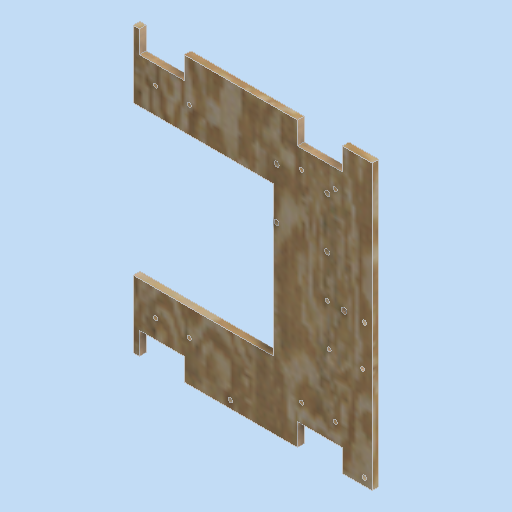
# Autodesk Inventor part: plateau_grand_robot
Saved by Autodesk Inventor 2026 (Build 300175050, 175E)
## iProperties
Created: 2025-05-01
Part Number: plateau_grand_robot
Material: Holz (Ahorn)
Document SubType Name: Modeling
Designer: karle
Density: 0.67 g/cm^3
Appearance: Ahorn - natur - glänzend - dunkel getönt
Author: karle
Autodesk Inventor part; units mm, degrees
ref_plane "YZ Plane" through (0, 0, 0) normal (1, 0, 0) x (0, 1, 0)
ref_plane "XZ Plane" through (0, 0, 0) normal (0, 1, 0) x (-1, 0, 0)
ref_plane "XY Plane" through (0, 0, 0) normal (0, 0, 1) x (1, 0, 0)
sketch "Skizze1" plane through (0, 0, 0) normal (0, 1, 0) x (-1, 0, 0)
  line L0 (175, 190) -> (-175, 190)
  line L1 (-175, 190) -> (-175, -190)
  line L2 (-175, -190) -> (175, -190)
  line L3 (175, -190) -> (175, 190)
  point P0 (0, 0)
  dimension "d0" = 380
  dimension "d1" = 350
  dimension "d2" = 175
  dimension "d3" = 190
  constraints: 8 end point, 2 parallel, 1 horizontal, 1 perpendicular
  measures "d0" distance between parallel lines of L2 L0
  measures "d1" distance of L1.end L2.end
  measures "d2" distance from line of point (0, 0) L3
  measures "d3" distance from line of L0 point (0, 0)
extrude "Extrusion1" add sketch "Skizze1" against normal blind 9
sketch "Skizze3" plane through (0, 0, 0) normal (0, 1, 0) x (1, 0, 0)
  line L0 (-175, 190) -> (-175, -190) projected
  line L1 (-175, -190) -> (175, -190) projected
  line L2 (175, 190) -> (175, -190) projected
  line L3 (175, -190) -> (-175, -190) projected
  line L4 (-175, -190) -> (-175, 190) projected
  line L5 (-175, 190) -> (175, 190) projected
  point P0 (0, 0)
  point P1 (165, 0)
  point P2 (115, 0)
  point P3 (-15, 180)
  point P4 (165, 180)
  point P5 (175, 0)
  dimension "d29" = 10
  dimension "d96" = 10
  dimension "d97" = 180
  dimension "d99" = 60
  dimension "d100" = 10
  dimension "d101" = 190
  constraints: 1 horizontal alignment, 1 midpoint, 1 vertical alignment
  measures "d29" distance from line of L5 point (165, 180)
  measures "d96" distance from line of point (-15, 180) L5
  measures "d97" distance of point (165, 180) point (-15, 180)
  measures "d99" distance of point (175, 0) point (115, 0)
  measures "d100" distance from line of L2 point (165, 0)
  measures "d101" distance from line of L5 point (115, 0)
hole "Bohrung2" at (165, 0, 0) at (115, 0, 0) at (-15, 0, -180) at (165, 0, -180) direction (0, -1, 0) diameter 6 end through all
sketch "Skizze4" plane through (0, -9, 0) normal (0, -1, 0) x (1, 0, 0)
  line L0 (-175, -190) -> (175, -190) projected
  line L1 (-175, 190) -> (-175, -190) projected
  line L2 (175, 190) -> (-175, 190) projected
  line L3 (175, -190) -> (175, 190) projected
  point P0 (0, 0)
  point P1 (115, 125)
  point P2 (115, 57)
  point P3 (47, 57)
  point P4 (47, 125)
  dimension "d30" = 68
  dimension "d31" = 68
  dimension "d41" = 65
  dimension "d42" = 60
  constraints: 2 horizontal alignment, 2 vertical alignment
  measures "d30" distance of point (115, 57) point (115, 125)
  measures "d31" distance of point (115, 57) point (47, 57)
  measures "d41" distance from line of L2 point (115, 125)
  measures "d42" distance from line of L3 point (115, 57)
hole "Bohrung3" at (115, -9, 125) at (115, -9, 57) at (47, -9, 57) at (47, -9, 125) direction (0, 1, 0) diameter 7 end through all
sketch "Skizze6" plane through (0, 0, 0) normal (0, 1, 0) x (1, 0, 0)
  line L0 (-175, 190) -> (-175, -190) projected
  line L1 (-175, -100) -> (42.5, -100)
  line L2 (42.5, -100) -> (42.5, 100)
  line L3 (42.5, 100) -> (-175, 100)
  line L4 (-175, 100) -> (-175, -100)
  line L5 (-175, -190) -> (-145, -190)
  line L6 (-145, -190) -> (-145, -100)
  line L7 (-145, -100) -> (-175, -100)
  line L8 (-175, -100) -> (-175, -190)
  line L9 (-175, 190) -> (-145, 190)
  line L10 (-145, 190) -> (-145, 100)
  line L11 (-145, 100) -> (-175, 100)
  line L12 (-175, 100) -> (-175, 190)
  point P0 (0, 0)
  dimension "d48" = 100
  dimension "d49" = 200
  dimension "d50" = 217.5
  dimension "d112" = 30
  dimension "d113" = 30
  constraints: 24 end point, 6 parallel, 3 horizontal, 3 perpendicular, 3 point on line
  measures "d48" distance from line of point (0, 0) L1
  measures "d49" distance between parallel lines of L1 L3
  measures "d50" distance between parallel lines of L0 L2
  measures "d112" distance between parallel lines of L0 L6
  measures "d113" distance between parallel lines of L0 L10
extrude "Extrusion3" cut sketch "Skizze6" against normal blind 88
sketch "Sketch11" plane through (0, 0, 0) normal (0, 1, 0) x (1, 0, 0)
  line L0 (79.1821, 0) -> (171.9168, 0) construction
  line L1 (175, -190) -> (175, 190) construction
  point P0 (0, 0)
  point P1 (137.5, 0)
  dimension "d117" = 37.5
  constraints: 2 end point, 1 horizontal, 1 point on line
  measures "d117" distance from line of L1 point (137.5, 0)
hole "Hole8" at (137.5, 0, 0) direction (0, -1, 0) diameter 8 end through all
sketch "Sketch10" plane through (0, 0, 0) normal (0, 1, 0) x (1, 0, 0)
  line L0 (-115, -135) -> (-70, -135) construction
  line L1 (5.2625, -294.5203) -> (5.2625, 225.0772) construction
  line L2 (-230.0493, 0) -> (259.3232, 0) construction
  line L3 (-175, -190) -> (175, -190) construction
  line L4 (-175, -100) -> (-175, -190) construction
  line L5 (125.525, -135) -> (80.525, -135) construction
  line L6 (-115, 135) -> (-70, 135) construction
  line L7 (125.525, 135) -> (80.525, 135) construction
  line L8 (117.5, 55) -> (162.5, 55) construction
  line L9 (175, 190) -> (-145, 190) construction
  line L10 (175, -190) -> (175, 190) construction
  line L11 (-145, -190) -> (-145, -100) projected
  point P0 (0, 0)
  dimension "d102" = 55
  dimension "d103" = 45
  dimension "d114" = 135
  dimension "d115" = 45
  dimension "d116" = 12.5
  dimension "d143" = 30
  dimension "d144" = 49.475
  constraints: 14 end point, 12 symmetric about line, 10 coincident, 3 horizontal, 1 vertical
  measures "d102" distance between parallel lines of L3 L0
  measures "d103" distance of point (-70, -135) point (-115, -135)
  measures "d114" distance between parallel lines of L9 L8
  measures "d115" distance of L8.start L8.end
  measures "d116" distance from line of L10 point (162.5, 55)
  measures "d143" distance from line of point (-115, -135) L11
  measures "d144" distance from line of L10 point (125.525, 135)
hole "Hole7" at (-115, 0, 135) at (-70, 0, 135) at (80.525, 0, 135) at (125.525, 0, 135) at (-70, 0, -135) at (-115, 0, -135) at (125.525, 0, -135) at (80.525, 0, -135) at (162.5, 0, -55) at (117.5, 0, -55) direction (0, -1, 0) diameter 5.5 end through all
sketch "Skizze12" plane through (0, -9, 0) normal (0, -1, 0) x (1, 0, 0)
  line L0 (-145, -190) -> (175, -190) projected
  line L1 (-136.725, -190) -> (-76.725, -190)
  line L2 (-76.725, -190) -> (-76.725, -160)
  line L3 (-76.725, -160) -> (-136.725, -160)
  line L4 (-136.725, -160) -> (-136.725, -190)
  line L5 (75, -190) -> (135, -190)
  line L6 (135, -190) -> (135, -160)
  line L7 (135, -160) -> (75, -160)
  line L8 (75, -160) -> (75, -190)
  line L9 (175, 190) -> (-145, 190) projected
  line L10 (-136.725, 190) -> (-76.725, 190)
  line L11 (-76.725, 190) -> (-76.725, 160)
  line L12 (-76.725, 160) -> (-136.725, 160)
  line L13 (-136.725, 160) -> (-136.725, 190)
  line L14 (75, 190) -> (135, 190)
  line L15 (135, 190) -> (135, 160)
  line L16 (135, 160) -> (75, 160)
  line L17 (75, 160) -> (75, 190)
  circle A0 centre (-70, 135) radius 2.75 projected
  circle A1 centre (-115, 135) radius 2.75 projected
  circle A2 centre (125.525, 135) radius 2.75 projected
  line L18 (-145, 190) -> (-145, 100) projected
  line L19 (175, -190) -> (175, 190) projected
  point P0 (0, 0)
  point P1 (-76.725, -175)
  point P2 (-106.725, -190)
  point P3 (135, -190)
  point P4 (135, 175)
  point P5 (135, -175)
  point P6 (-76.725, 175)
  point P7 (115.5816, 121.5487)
  point P8 (112.7354, 122.3314)
  dimension "d125" = 60
  dimension "d130" = 30
  dimension "d132" = 60
  dimension "d134" = 30
  dimension "d135" = 60
  dimension "d141" = 8.275
  dimension "d142" = 40
  constraints: 32 end point, 8 parallel, 5 midpoint, 5 point on line, 4 equal length, 4 horizontal, 4 perpendicular, 2 vertical alignment, 1 other
  measures "d125" distance between parallel lines of L11 L13
  measures "d130" distance between parallel lines of L9 L12
  measures "d132" distance from line of point (-76.725, -175) L4
  measures "d134" distance from line of point (-106.725, -190) L3
  measures "d135" distance between parallel lines of L6 L8
  measures "d141" distance between parallel lines of L18 L13
  measures "d142" distance between parallel lines of L19 L15
extrude "Extrusion4" cut sketch "Skizze12" against normal through all contours L4 L3 L2 L0 | L11 L12 L13 L9 | L15 L16 L17 L9 | L8 L7 L6 L0
equation "\"d132\" = d125"
